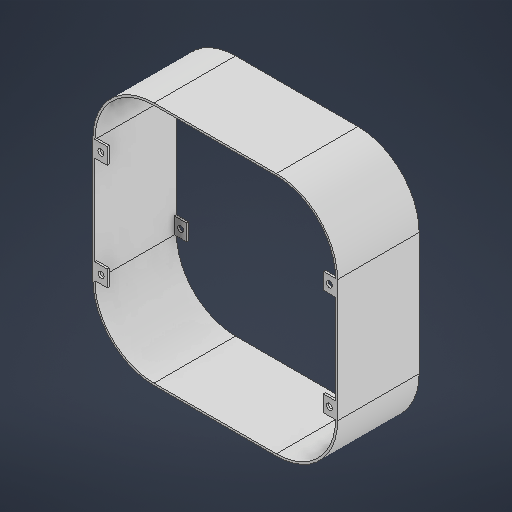
# Autodesk Inventor part: sides cover
Saved by Autodesk Inventor 2025.2 (Build 292293000, 293)
## iProperties
Created: 2024-12-25
Part Number: sides cover
Material: Generic
Document SubType Name: Modeling
Designer: user
Density: 1 g/cm^3
Appearance: Default
Author: user
Autodesk Inventor part; units mm, degrees
sketch "Sketch1" plane through (0, 0, 0) normal (0, 0, 1) x (1, 0, 0)
  circle A0 centre (0, 0) radius 300
  line L0 (150, 300) -> (-150, 300)
  line L1 (-300, 150) -> (-300, -150)
  line L2 (-150, -300) -> (150, -300)
  line L3 (300, -150) -> (300, 150)
  line L4 (300, 300) -> (-300, -300) construction
  line L5 (-300, 300) -> (300, -300) construction
  arc A1 (300, 150) -> (150, 300) centre (150, 150) ccw
  arc A2 (-150, 300) -> (-300, 150) centre (-150, 150) ccw
  arc A3 (-300, -150) -> (-150, -300) centre (-150, -150) ccw
  arc A4 (150, -300) -> (300, -150) centre (150, -150) ccw
  point P0 (300, 0)
  point P1 (0, -300)
  point P2 (-300, 0)
  point P3 (0, 300)
  dimension "d0" = 600
  dimension "d8" = 600
  dimension "d9" = 150
  constraints: 12 end point, 8 point on circle, 8 point on line, 8 tangent, 5 centre point, 3 equal radius, 2 midpoint, 2 parallel, 1 coincident, 1 horizontal, 1 perpendicular
  measures "d0" diameter of A0
  measures "d8" distance of L4.end L5.start
  measures "d9" radius of A1
ref_plane "Work Plane2" through (0, 0, 5) normal (0, 0, 1) x (1, 0, 0)
sketch "Sketch3" plane through (0, 0, 5) normal (0, 0, 1) x (1, 0, 0)
  line L0 (150, 300) -> (-150, 300) projected
  arc A0 (-150, 300) -> (-300, 150) centre (-150, 150) ccw projected
  line L1 (-300, 150) -> (-300, -150) projected
  arc A1 (-300, -150) -> (-150, -300) centre (-150, -150) ccw projected
  line L2 (-150, -300) -> (150, -300) projected
  arc A2 (150, -300) -> (300, -150) centre (150, -150) ccw projected
  line L3 (300, -150) -> (300, 150) projected
  arc A3 (300, 150) -> (150, 300) centre (150, 150) ccw projected
  arc A4 (-150, 295) -> (-295, 150) centre (-150, 150) ccw
  line L4 (-150, 295) -> (150, 295)
  arc A5 (295, 150) -> (150, 295) centre (150, 150) ccw
  line L5 (295, 150) -> (295, -150)
  arc A6 (150, -295) -> (295, -150) centre (150, -150) ccw
  line L6 (150, -295) -> (-150, -295)
  arc A7 (-295, -150) -> (-150, -295) centre (-150, -150) ccw
  line L7 (-295, -150) -> (-295, 150)
  point P0 (0, 0)
  dimension "d10" = 5
  constraints: 8 end point, 8 point on circle, 4 centre point, 7 other
  measures "d10" radial gap between concentric circles of A0 A4
extrude "Extrusion3" add sketch "Sketch3" along normal blind 200
ref_plane "Work Plane1" through (0, 0, 5) normal (0, 0, 1) x (1, 0, 0)
sketch "Sketch4" plane through (0, 0, 5) normal (0, 0, 1) x (1, 0, 0)
  point P0 (0, 0)
sketch "Sketch5" plane through (-295, -150, 5) normal (1, 0, 0) x (0, 0, -1)
  line L0 (-200, 300) -> (-200, 0) projected
  line L1 (-200, 300) -> (-195, 300)
  line L2 (-195, 300) -> (-195, 260)
  line L3 (-195, 260) -> (-200, 260)
  line L4 (-200, 260) -> (-200, 300)
  line L5 (-200, 150) -> (0, 150) construction
  line L6 (0, 300) -> (0, 0) construction
  point P0 (5, 150)
  dimension "d13" = 5
  dimension "d14" = 40
  constraints: 10 end point, 2 midpoint, 2 parallel, 1 horizontal, 1 perpendicular
  measures "d13" distance of L2.end L3.end
  measures "d14" distance of L1.end L2.end
extrude "Extrusion4" add sketch "Sketch5" along normal blind 30
mirror "Mirror1" about plane through (0, 0, 0) normal (1, 0, 0) of "Extrusion4"
mirror "Mirror2" about plane through (0, 0, 0) normal (0, 1, 0) of "Extrusion4", "Mirror1"
sketch "Sketch6" plane through (0, 0, 205) normal (0, 0, 1) x (1, 0, 0)
  line L0 (-295, 150) -> (-265, 150) construction
  line L1 (-295, 150) -> (-265, 150) construction
  line L2 (-265, 150) -> (-265, 110) construction
  line L3 (-265, 150) -> (-265, 110) construction
  line L4 (-265, 110) -> (-295, 110) construction
  line L5 (-295, 110) -> (-295, 150) construction
  line L6 (-295, 130) -> (-265, 130) construction
  line L7 (-295, 130) -> (-280, 130)
  circle A0 centre (-280, 130) radius 7.5
  line L8 (-300, 150) -> (-300, -150) projected
  point P0 (0, 0)
  dimension "d44" = 15
  dimension "d48" = 20
  constraints: 12 end point, 3 midpoint, 2 perpendicular, 1 centre point, 1 collinear, 1 horizontal, 1 point on line
  measures "d44" diameter of A0
  measures "d48" distance from line of L8 A0.centre
ref_plane "Work Plane3" through (0, 0, 105) normal (0, 0, 1) x (1, 0, 0)
extrude "Extrusion6" cut sketch "Sketch6" against normal blind 30
pattern_linear "Rectangular Pattern1" count 2 spacing 560 along (1, 0, 0) count 2 spacing 260 along (0, -1, 0) of "Extrusion6"
ref_plane "Work Plane4" through (0, 0, 105) normal (0, 0, 1) x (1, 0, 0)
mirror "Mirror4" about plane through (0, 0, 105) normal (0, 0, 1) of "Extrusion4", "Extrusion6", "Mirror1", "Mirror2", "Rectangular Pattern1"
body "Solid1"
